Autodesk Fusion 360 part; units mm, degrees
(part 7 of 8)
equation "d2050 = ( ( layoutGap + keycapSize / 2 + 1 * keyPitch ) - holderStemX ) + ( 3 mm ) - 0.5 mm"
equation "d2051 = ( ( ( keyRowOne ) - holderStemY ) + 4 mm ) + faceOriginV"
equation "d2052 = ( ( ( ( layoutGap + keycapSize / 2 + 1 * keyPitch ) - holderStemX ) + ( 3 mm ) - 0.5 mm ) + ( 1 mm ) ) - ( ( ( layoutGap + keycapSize / 2 + 1 * keyPitch ) - holderStemX ) + ( 3 mm ) - 0.5 mm )"
equation "d2053 = ( ( ( ( ( keyRowOne ) - holderStemY ) + 4 mm ) + faceOriginV ) + ( holderFrameY / 2 - 4 mm ) ) - ( ( ( ( keyRowOne ) - holderStemY ) + 4 mm ) + faceOriginV )"
equation "d2056 = ( ( layoutGap + keycapSize / 2 + 1 * keyPitch ) - holderStemX ) - holderFrameX / 2 - 0.1 mm"
equation "d2057 = ( ( ( keyRowOne ) - holderStemY ) - 5.1 mm ) + faceOriginV"
equation "d2058 = ( ( ( ( layoutGap + keycapSize / 2 + 1 * keyPitch ) - holderStemX ) - holderFrameX / 2 - 0.1 mm ) + ( holderFrameX / 2 - holderWidth / 2 + 0.1 mm ) ) - ( ( ( layoutGap + keycapSize / 2 + 1 * keyPitch ) - holderStemX ) - holderFrameX / 2 - 0.1 mm )"
equation "d2059 = ( ( ( ( ( keyRowOne ) - holderStemY ) - 5.1 mm ) + faceOriginV ) + ( 7.8 mm ) ) - ( ( ( ( keyRowOne ) - holderStemY ) - 5.1 mm ) + faceOriginV )"
equation "d2060 = -( holderHeight + holderHookThickness - 1.2 mm + 0.2 mm )"
equation "d2062 = ( ( layoutGap + keycapSize / 2 + 1 * keyPitch ) - holderStemX ) + holderWidth / 2"
equation "d2063 = ( ( ( keyRowOne ) - holderStemY ) - 5.1 mm ) + faceOriginV"
equation "d2064 = ( ( ( ( layoutGap + keycapSize / 2 + 1 * keyPitch ) - holderStemX ) + holderWidth / 2 ) + ( holderFrameX / 2 - holderWidth / 2 + 0.1 mm ) ) - ( ( ( layoutGap + keycapSize / 2 + 1 * keyPitch ) - holderStemX ) + holderWidth / 2 )"
equation "d2065 = ( ( ( ( ( keyRowOne ) - holderStemY ) - 5.1 mm ) + faceOriginV ) + ( 7.8 mm ) ) - ( ( ( ( keyRowOne ) - holderStemY ) - 5.1 mm ) + faceOriginV )"
equation "d2066 = -( holderHeight + holderHookThickness - 1.2 mm + 0.2 mm )"
equation "d2068 = ( ( layoutGap + keycapSize / 2 + 1 * keyPitch ) - holderStemX ) + ( -2.5 mm ) - 1.2 mm"
equation "d2069 = ( ( ( ( keyRowOne ) - holderStemY ) - 1.2 mm ) * cos(caseTilt) + ( holderBottomDepth + holderLidGap ) * sin(caseTilt) ) - 2.5 mm"
equation "d2070 = ( ( ( ( layoutGap + keycapSize / 2 + 1 * keyPitch ) - holderStemX ) + ( -2.5 mm ) - 1.2 mm ) + ( 2.4 mm ) ) - ( ( ( layoutGap + keycapSize / 2 + 1 * keyPitch ) - holderStemX ) + ( -2.5 mm ) - 1.2 mm )"
equation "d2071 = ( ( ( ( ( ( keyRowOne ) - holderStemY ) - 1.2 mm ) * cos(caseTilt) + ( holderBottomDepth + holderLidGap ) * sin(caseTilt) ) - 2.5 mm ) + ( 5 mm ) ) - ( ( ( ( ( keyRowOne ) - holderStemY ) - 1.2 mm ) * cos(caseTilt) + ( holderBottomDepth + holderLidGap ) * sin(caseTilt) ) - 2.5 mm )"
equation "d2072 = ( frontHeight + ( ( ( keyRowOne ) - holderStemY ) - 1.2 mm ) * sin(caseTilt) - ( holderBottomDepth + holderLidGap ) * cos(caseTilt) ) - bottomThickness - 2 mm"
equation "d2074 = ( ( layoutGap + keycapSize / 2 + 1 * keyPitch ) - holderStemX ) + ( -2.5 mm ) - 0.5 mm"
equation "d2075 = ( ( ( ( keyRowOne ) - holderStemY ) - 1.2 mm ) * cos(caseTilt) + ( holderBottomDepth + holderLidGap ) * sin(caseTilt) ) - 1.5 mm"
equation "d2076 = ( ( ( ( layoutGap + keycapSize / 2 + 1 * keyPitch ) - holderStemX ) + ( -2.5 mm ) - 0.5 mm ) + ( 1 mm ) ) - ( ( ( layoutGap + keycapSize / 2 + 1 * keyPitch ) - holderStemX ) + ( -2.5 mm ) - 0.5 mm )"
equation "d2077 = ( ( ( ( ( ( keyRowOne ) - holderStemY ) - 1.2 mm ) * cos(caseTilt) + ( holderBottomDepth + holderLidGap ) * sin(caseTilt) ) - 1.5 mm ) + ( 3 mm ) ) - ( ( ( ( ( keyRowOne ) - holderStemY ) - 1.2 mm ) * cos(caseTilt) + ( holderBottomDepth + holderLidGap ) * sin(caseTilt) ) - 1.5 mm )"
equation "d2078 = ( frontHeight + ( ( ( keyRowOne ) - holderStemY ) - 1.2 mm ) * sin(caseTilt) - ( holderBottomDepth + holderLidGap ) * cos(caseTilt) ) - bottomThickness + 0.5 mm"
equation "d2080 = ( ( ( layoutGap + keycapSize / 2 + 1 * keyPitch ) - holderStemX ) + ( -2.5 mm ) - 0.5 mm ) - 0.1 mm"
equation "d2081 = ( ( ( ( keyRowOne ) - holderStemY ) - 1.2 mm ) - 2 mm ) + faceOriginV"
equation "d2082 = ( ( ( ( ( layoutGap + keycapSize / 2 + 1 * keyPitch ) - holderStemX ) + ( -2.5 mm ) - 0.5 mm ) - 0.1 mm ) + ( 1.2 mm ) ) - ( ( ( ( layoutGap + keycapSize / 2 + 1 * keyPitch ) - holderStemX ) + ( -2.5 mm ) - 0.5 mm ) - 0.1 mm )"
equation "d2083 = ( ( ( ( ( ( keyRowOne ) - holderStemY ) - 1.2 mm ) - 2 mm ) + faceOriginV ) + ( 4 mm ) ) - ( ( ( ( ( keyRowOne ) - holderStemY ) - 1.2 mm ) - 2 mm ) + faceOriginV )"
equation "d2084 = rearHeight"
equation "d2086 = ( ( layoutGap + keycapSize / 2 + 1 * keyPitch ) - holderStemX ) + ( 2.5 mm ) - 1.2 mm"
equation "d2087 = ( ( ( ( keyRowOne ) - holderStemY ) - 1.2 mm ) * cos(caseTilt) + ( holderBottomDepth + holderLidGap ) * sin(caseTilt) ) - 2.5 mm"
equation "d2088 = ( ( ( ( layoutGap + keycapSize / 2 + 1 * keyPitch ) - holderStemX ) + ( 2.5 mm ) - 1.2 mm ) + ( 2.4 mm ) ) - ( ( ( layoutGap + keycapSize / 2 + 1 * keyPitch ) - holderStemX ) + ( 2.5 mm ) - 1.2 mm )"
equation "d2089 = ( ( ( ( ( ( keyRowOne ) - holderStemY ) - 1.2 mm ) * cos(caseTilt) + ( holderBottomDepth + holderLidGap ) * sin(caseTilt) ) - 2.5 mm ) + ( 5 mm ) ) - ( ( ( ( ( keyRowOne ) - holderStemY ) - 1.2 mm ) * cos(caseTilt) + ( holderBottomDepth + holderLidGap ) * sin(caseTilt) ) - 2.5 mm )"
equation "d2090 = ( frontHeight + ( ( ( keyRowOne ) - holderStemY ) - 1.2 mm ) * sin(caseTilt) - ( holderBottomDepth + holderLidGap ) * cos(caseTilt) ) - bottomThickness - 2 mm"
equation "d2092 = ( ( layoutGap + keycapSize / 2 + 1 * keyPitch ) - holderStemX ) + ( 2.5 mm ) - 0.5 mm"
equation "d2093 = ( ( ( ( keyRowOne ) - holderStemY ) - 1.2 mm ) * cos(caseTilt) + ( holderBottomDepth + holderLidGap ) * sin(caseTilt) ) - 1.5 mm"
equation "d2094 = ( ( ( ( layoutGap + keycapSize / 2 + 1 * keyPitch ) - holderStemX ) + ( 2.5 mm ) - 0.5 mm ) + ( 1 mm ) ) - ( ( ( layoutGap + keycapSize / 2 + 1 * keyPitch ) - holderStemX ) + ( 2.5 mm ) - 0.5 mm )"
equation "d2095 = ( ( ( ( ( ( keyRowOne ) - holderStemY ) - 1.2 mm ) * cos(caseTilt) + ( holderBottomDepth + holderLidGap ) * sin(caseTilt) ) - 1.5 mm ) + ( 3 mm ) ) - ( ( ( ( ( keyRowOne ) - holderStemY ) - 1.2 mm ) * cos(caseTilt) + ( holderBottomDepth + holderLidGap ) * sin(caseTilt) ) - 1.5 mm )"
equation "d2096 = ( frontHeight + ( ( ( keyRowOne ) - holderStemY ) - 1.2 mm ) * sin(caseTilt) - ( holderBottomDepth + holderLidGap ) * cos(caseTilt) ) - bottomThickness + 0.5 mm"
equation "d2098 = ( ( ( layoutGap + keycapSize / 2 + 1 * keyPitch ) - holderStemX ) + ( 2.5 mm ) - 0.5 mm ) - 0.1 mm"
equation "d2099 = ( ( ( ( keyRowOne ) - holderStemY ) - 1.2 mm ) - 2 mm ) + faceOriginV"
equation "d2100 = ( ( ( ( ( layoutGap + keycapSize / 2 + 1 * keyPitch ) - holderStemX ) + ( 2.5 mm ) - 0.5 mm ) - 0.1 mm ) + ( 1.2 mm ) ) - ( ( ( ( layoutGap + keycapSize / 2 + 1 * keyPitch ) - holderStemX ) + ( 2.5 mm ) - 0.5 mm ) - 0.1 mm )"
equation "d2101 = ( ( ( ( ( ( keyRowOne ) - holderStemY ) - 1.2 mm ) - 2 mm ) + faceOriginV ) + ( 4 mm ) ) - ( ( ( ( ( keyRowOne ) - holderStemY ) - 1.2 mm ) - 2 mm ) + faceOriginV )"
equation "d2102 = rearHeight"
equation "d2104 = ( layoutGap + keycapSize / 2 + 2 * keyPitch ) - holderFrameX / 2"
equation "d2105 = ( ( keyRowOne ) - holderFrameY / 2 ) + faceOriginV"
equation "d2106 = ( ( ( layoutGap + keycapSize / 2 + 2 * keyPitch ) - holderFrameX / 2 ) + ( holderFrameX ) ) - ( ( layoutGap + keycapSize / 2 + 2 * keyPitch ) - holderFrameX / 2 )"
equation "d2107 = ( ( ( ( keyRowOne ) - holderFrameY / 2 ) + faceOriginV ) + ( holderFrameY ) ) - ( ( ( keyRowOne ) - holderFrameY / 2 ) + faceOriginV )"
equation "d2108 = -( holderBottomDepth + holderHookThickness - shellWall - carrierClearance - carrierThickness )"
equation "d2110 = ( layoutGap + keycapSize / 2 + 2 * keyPitch ) - holderSwitchVoid / 2"
equation "d2111 = ( ( keyRowOne ) - holderSwitchVoid / 2 ) + faceOriginV"
equation "d2112 = ( ( ( layoutGap + keycapSize / 2 + 2 * keyPitch ) - holderSwitchVoid / 2 ) + ( holderSwitchVoid ) ) - ( ( layoutGap + keycapSize / 2 + 2 * keyPitch ) - holderSwitchVoid / 2 )"
equation "d2113 = ( ( ( ( keyRowOne ) - holderSwitchVoid / 2 ) + faceOriginV ) + ( holderSwitchVoid ) ) - ( ( ( keyRowOne ) - holderSwitchVoid / 2 ) + faceOriginV )"
equation "d2114 = -( holderTopDepth - shellWall - carrierClearance - carrierThickness )"
equation "d2116 = ( ( layoutGap + keycapSize / 2 + 2 * keyPitch ) - holderStemX ) - holderWidth / 2 - holderFit"
equation "d2117 = ( ( ( keyRowOne ) - holderStemY ) - holderLength / 2 - holderFit ) + faceOriginV"
equation "d2118 = ( ( ( ( layoutGap + keycapSize / 2 + 2 * keyPitch ) - holderStemX ) - holderWidth / 2 - holderFit ) + ( holderWidth + 2 * holderFit ) ) - ( ( ( layoutGap + keycapSize / 2 + 2 * keyPitch ) - holderStemX ) - holderWidth / 2 - holderFit )"
equation "d2119 = ( ( ( ( ( keyRowOne ) - holderStemY ) - holderLength / 2 - holderFit ) + faceOriginV ) + ( holderLength + 2 * holderFit ) ) - ( ( ( ( keyRowOne ) - holderStemY ) - holderLength / 2 - holderFit ) + faceOriginV )"
equation "d2120 = -( holderHeight + holderHookThickness + 0.2 mm )"
equation "d2122 = ( ( layoutGap + keycapSize / 2 + 2 * keyPitch ) - holderStemX ) - holderFrameX / 2 - 0.1 mm"
equation "d2123 = ( ( ( ( keyRowOne ) - holderStemY ) + holderSpringY ) - holderSpringWidth / 2 - 0.6 mm ) + faceOriginV"
equation "d2124 = ( ( ( ( layoutGap + keycapSize / 2 + 2 * keyPitch ) - holderStemX ) - holderFrameX / 2 - 0.1 mm ) + ( holderFrameX / 2 - holderWidth / 2 - holderFit + 0.1 mm ) ) - ( ( ( layoutGap + keycapSize / 2 + 2 * keyPitch ) - holderStemX ) - holderFrameX / 2 - 0.1 mm )"
equation "d2125 = ( ( ( ( ( ( keyRowOne ) - holderStemY ) + holderSpringY ) - holderSpringWidth / 2 - 0.6 mm ) + faceOriginV ) + ( 0.6 mm ) ) - ( ( ( ( ( keyRowOne ) - holderStemY ) + holderSpringY ) - holderSpringWidth / 2 - 0.6 mm ) + faceOriginV )"
equation "d2126 = -( holderBottomDepth + holderHookThickness - shellWall - carrierClearance - carrierThickness - 1 mm + 0.2 mm )"
equation "d2128 = ( ( layoutGap + keycapSize / 2 + 2 * keyPitch ) - holderStemX ) - holderFrameX / 2 - 0.1 mm"
equation "d2129 = ( ( ( ( keyRowOne ) - holderStemY ) + holderSpringY ) + holderSpringWidth / 2 ) + faceOriginV"
equation "d2130 = ( ( ( ( layoutGap + keycapSize / 2 + 2 * keyPitch ) - holderStemX ) - holderFrameX / 2 - 0.1 mm ) + ( holderFrameX / 2 - holderWidth / 2 - holderFit + 0.1 mm ) ) - ( ( ( layoutGap + keycapSize / 2 + 2 * keyPitch ) - holderStemX ) - holderFrameX / 2 - 0.1 mm )"
equation "d2131 = ( ( ( ( ( ( keyRowOne ) - holderStemY ) + holderSpringY ) + holderSpringWidth / 2 ) + faceOriginV ) + ( 0.6 mm ) ) - ( ( ( ( ( keyRowOne ) - holderStemY ) + holderSpringY ) + holderSpringWidth / 2 ) + faceOriginV )"
equation "d2132 = -( holderBottomDepth + holderHookThickness - shellWall - carrierClearance - carrierThickness - 1 mm + 0.2 mm )"
equation "d2134 = ( ( layoutGap + keycapSize / 2 + 2 * keyPitch ) - holderStemX ) - holderFrameX / 2 + 0.8 mm"
equation "d2135 = ( ( ( ( keyRowOne ) - holderStemY ) + holderSpringY ) - holderSpringWidth / 2 ) + faceOriginV"
equation "d2136 = ( ( ( ( layoutGap + keycapSize / 2 + 2 * keyPitch ) - holderStemX ) - holderFrameX / 2 + 0.8 mm ) + ( holderFrameX / 2 - 0.8 mm - holderWidth / 2 - holderFit ) ) - ( ( ( layoutGap + keycapSize / 2 + 2 * keyPitch ) - holderStemX ) - holderFrameX / 2 + 0.8 mm )"
equation "d2137 = ( ( ( ( ( ( keyRowOne ) - holderStemY ) + holderSpringY ) - holderSpringWidth / 2 ) + faceOriginV ) + ( holderSpringWidth ) ) - ( ( ( ( ( keyRowOne ) - holderStemY ) + holderSpringY ) - holderSpringWidth / 2 ) + faceOriginV )"
equation "d2138 = -( holderHeight + holderHookThickness + 0.2 mm )"
equation "d2140 = ( ( layoutGap + keycapSize / 2 + 2 * keyPitch ) - holderStemX ) - holderFrameX / 2"
equation "d2141 = ( ( ( ( keyRowOne ) - holderStemY ) + holderSpringY ) - holderSpringWidth / 2 ) + faceOriginV"
equation "d2142 = ( ( ( ( layoutGap + keycapSize / 2 + 2 * keyPitch ) - holderStemX ) - holderFrameX / 2 ) + ( holderFrameX / 2 - holderWidth / 2 + holderHookOverlap ) ) - ( ( ( layoutGap + keycapSize / 2 + 2 * keyPitch ) - holderStemX ) - holderFrameX / 2 )"
equation "d2143 = ( ( ( ( ( ( keyRowOne ) - holderStemY ) + holderSpringY ) - holderSpringWidth / 2 ) + faceOriginV ) + ( holderSpringWidth ) ) - ( ( ( ( ( keyRowOne ) - holderStemY ) + holderSpringY ) - holderSpringWidth / 2 ) + faceOriginV )"
equation "d2144 = -( holderHookThickness )"
equation "d2147 = ( ( layoutGap + keycapSize / 2 + 2 * keyPitch ) - holderStemX ) + holderWidth / 2 + holderFit"
equation "d2148 = ( ( ( ( keyRowOne ) - holderStemY ) + holderSpringY ) - holderSpringWidth / 2 - 0.6 mm ) + faceOriginV"
equation "d2149 = ( ( ( ( layoutGap + keycapSize / 2 + 2 * keyPitch ) - holderStemX ) + holderWidth / 2 + holderFit ) + ( holderFrameX / 2 - holderWidth / 2 - holderFit + 0.1 mm ) ) - ( ( ( layoutGap + keycapSize / 2 + 2 * keyPitch ) - holderStemX ) + holderWidth / 2 + holderFit )"
equation "d2150 = ( ( ( ( ( ( keyRowOne ) - holderStemY ) + holderSpringY ) - holderSpringWidth / 2 - 0.6 mm ) + faceOriginV ) + ( 0.6 mm ) ) - ( ( ( ( ( keyRowOne ) - holderStemY ) + holderSpringY ) - holderSpringWidth / 2 - 0.6 mm ) + faceOriginV )"
equation "d2151 = -( holderBottomDepth + holderHookThickness - shellWall - carrierClearance - carrierThickness - 1 mm + 0.2 mm )"
equation "d2153 = ( ( layoutGap + keycapSize / 2 + 2 * keyPitch ) - holderStemX ) + holderWidth / 2 + holderFit"
equation "d2154 = ( ( ( ( keyRowOne ) - holderStemY ) + holderSpringY ) + holderSpringWidth / 2 ) + faceOriginV"
equation "d2155 = ( ( ( ( layoutGap + keycapSize / 2 + 2 * keyPitch ) - holderStemX ) + holderWidth / 2 + holderFit ) + ( holderFrameX / 2 - holderWidth / 2 - holderFit + 0.1 mm ) ) - ( ( ( layoutGap + keycapSize / 2 + 2 * keyPitch ) - holderStemX ) + holderWidth / 2 + holderFit )"
equation "d2156 = ( ( ( ( ( ( keyRowOne ) - holderStemY ) + holderSpringY ) + holderSpringWidth / 2 ) + faceOriginV ) + ( 0.6 mm ) ) - ( ( ( ( ( keyRowOne ) - holderStemY ) + holderSpringY ) + holderSpringWidth / 2 ) + faceOriginV )"
equation "d2157 = -( holderBottomDepth + holderHookThickness - shellWall - carrierClearance - carrierThickness - 1 mm + 0.2 mm )"
equation "d2159 = ( ( layoutGap + keycapSize / 2 + 2 * keyPitch ) - holderStemX ) + holderWidth / 2 + holderFit"
equation "d2160 = ( ( ( ( keyRowOne ) - holderStemY ) + holderSpringY ) - holderSpringWidth / 2 ) + faceOriginV"
equation "d2161 = ( ( ( ( layoutGap + keycapSize / 2 + 2 * keyPitch ) - holderStemX ) + holderWidth / 2 + holderFit ) + ( holderFrameX / 2 - 0.8 mm - holderWidth / 2 - holderFit ) ) - ( ( ( layoutGap + keycapSize / 2 + 2 * keyPitch ) - holderStemX ) + holderWidth / 2 + holderFit )"
equation "d2162 = ( ( ( ( ( ( keyRowOne ) - holderStemY ) + holderSpringY ) - holderSpringWidth / 2 ) + faceOriginV ) + ( holderSpringWidth ) ) - ( ( ( ( ( keyRowOne ) - holderStemY ) + holderSpringY ) - holderSpringWidth / 2 ) + faceOriginV )"
equation "d2163 = -( holderHeight + holderHookThickness + 0.2 mm )"
equation "d2165 = ( ( layoutGap + keycapSize / 2 + 2 * keyPitch ) - holderStemX ) + holderWidth / 2 - holderHookOverlap"
equation "d2166 = ( ( ( ( keyRowOne ) - holderStemY ) + holderSpringY ) - holderSpringWidth / 2 ) + faceOriginV"
equation "d2167 = ( ( ( ( layoutGap + keycapSize / 2 + 2 * keyPitch ) - holderStemX ) + holderWidth / 2 - holderHookOverlap ) + ( holderFrameX / 2 - holderWidth / 2 + holderHookOverlap ) ) - ( ( ( layoutGap + keycapSize / 2 + 2 * keyPitch ) - holderStemX ) + holderWidth / 2 - holderHookOverlap )"
equation "d2168 = ( ( ( ( ( ( keyRowOne ) - holderStemY ) + holderSpringY ) - holderSpringWidth / 2 ) + faceOriginV ) + ( holderSpringWidth ) ) - ( ( ( ( ( keyRowOne ) - holderStemY ) + holderSpringY ) - holderSpringWidth / 2 ) + faceOriginV )"
equation "d2169 = -( holderHookThickness )"
equation "d2172 = ( ( layoutGap + keycapSize / 2 + 2 * keyPitch ) - holderStemX ) + ( -3 mm ) - 0.5 mm"
equation "d2173 = ( ( ( keyRowOne ) - holderStemY ) + 4 mm ) + faceOriginV"
equation "d2174 = ( ( ( ( layoutGap + keycapSize / 2 + 2 * keyPitch ) - holderStemX ) + ( -3 mm ) - 0.5 mm ) + ( 1 mm ) ) - ( ( ( layoutGap + keycapSize / 2 + 2 * keyPitch ) - holderStemX ) + ( -3 mm ) - 0.5 mm )"
equation "d2175 = ( ( ( ( ( keyRowOne ) - holderStemY ) + 4 mm ) + faceOriginV ) + ( holderFrameY / 2 - 4 mm ) ) - ( ( ( ( keyRowOne ) - holderStemY ) + 4 mm ) + faceOriginV )"
equation "d2178 = ( ( layoutGap + keycapSize / 2 + 2 * keyPitch ) - holderStemX ) + ( 3 mm ) - 0.5 mm"
equation "d2179 = ( ( ( keyRowOne ) - holderStemY ) + 4 mm ) + faceOriginV"
equation "d2180 = ( ( ( ( layoutGap + keycapSize / 2 + 2 * keyPitch ) - holderStemX ) + ( 3 mm ) - 0.5 mm ) + ( 1 mm ) ) - ( ( ( layoutGap + keycapSize / 2 + 2 * keyPitch ) - holderStemX ) + ( 3 mm ) - 0.5 mm )"
equation "d2181 = ( ( ( ( ( keyRowOne ) - holderStemY ) + 4 mm ) + faceOriginV ) + ( holderFrameY / 2 - 4 mm ) ) - ( ( ( ( keyRowOne ) - holderStemY ) + 4 mm ) + faceOriginV )"
equation "d2184 = ( ( layoutGap + keycapSize / 2 + 2 * keyPitch ) - holderStemX ) - holderFrameX / 2 - 0.1 mm"
equation "d2185 = ( ( ( keyRowOne ) - holderStemY ) - 5.1 mm ) + faceOriginV"
equation "d2186 = ( ( ( ( layoutGap + keycapSize / 2 + 2 * keyPitch ) - holderStemX ) - holderFrameX / 2 - 0.1 mm ) + ( holderFrameX / 2 - holderWidth / 2 + 0.1 mm ) ) - ( ( ( layoutGap + keycapSize / 2 + 2 * keyPitch ) - holderStemX ) - holderFrameX / 2 - 0.1 mm )"
equation "d2187 = ( ( ( ( ( keyRowOne ) - holderStemY ) - 5.1 mm ) + faceOriginV ) + ( 7.8 mm ) ) - ( ( ( ( keyRowOne ) - holderStemY ) - 5.1 mm ) + faceOriginV )"
equation "d2188 = -( holderHeight + holderHookThickness - 1.2 mm + 0.2 mm )"
equation "d2190 = ( ( layoutGap + keycapSize / 2 + 2 * keyPitch ) - holderStemX ) + holderWidth / 2"
equation "d2191 = ( ( ( keyRowOne ) - holderStemY ) - 5.1 mm ) + faceOriginV"
equation "d2192 = ( ( ( ( layoutGap + keycapSize / 2 + 2 * keyPitch ) - holderStemX ) + holderWidth / 2 ) + ( holderFrameX / 2 - holderWidth / 2 + 0.1 mm ) ) - ( ( ( layoutGap + keycapSize / 2 + 2 * keyPitch ) - holderStemX ) + holderWidth / 2 )"
equation "d2193 = ( ( ( ( ( keyRowOne ) - holderStemY ) - 5.1 mm ) + faceOriginV ) + ( 7.8 mm ) ) - ( ( ( ( keyRowOne ) - holderStemY ) - 5.1 mm ) + faceOriginV )"
equation "d2194 = -( holderHeight + holderHookThickness - 1.2 mm + 0.2 mm )"
equation "d2196 = ( ( layoutGap + keycapSize / 2 + 2 * keyPitch ) - holderStemX ) + ( -2.5 mm ) - 1.2 mm"
equation "d2197 = ( ( ( ( keyRowOne ) - holderStemY ) - 1.2 mm ) * cos(caseTilt) + ( holderBottomDepth + holderLidGap ) * sin(caseTilt) ) - 2.5 mm"
equation "d2198 = ( ( ( ( layoutGap + keycapSize / 2 + 2 * keyPitch ) - holderStemX ) + ( -2.5 mm ) - 1.2 mm ) + ( 2.4 mm ) ) - ( ( ( layoutGap + keycapSize / 2 + 2 * keyPitch ) - holderStemX ) + ( -2.5 mm ) - 1.2 mm )"
equation "d2199 = ( ( ( ( ( ( keyRowOne ) - holderStemY ) - 1.2 mm ) * cos(caseTilt) + ( holderBottomDepth + holderLidGap ) * sin(caseTilt) ) - 2.5 mm ) + ( 5 mm ) ) - ( ( ( ( ( keyRowOne ) - holderStemY ) - 1.2 mm ) * cos(caseTilt) + ( holderBottomDepth + holderLidGap ) * sin(caseTilt) ) - 2.5 mm )"
equation "d2200 = ( frontHeight + ( ( ( keyRowOne ) - holderStemY ) - 1.2 mm ) * sin(caseTilt) - ( holderBottomDepth + holderLidGap ) * cos(caseTilt) ) - bottomThickness - 2 mm"
equation "d2202 = ( ( layoutGap + keycapSize / 2 + 2 * keyPitch ) - holderStemX ) + ( -2.5 mm ) - 0.5 mm"
equation "d2203 = ( ( ( ( keyRowOne ) - holderStemY ) - 1.2 mm ) * cos(caseTilt) + ( holderBottomDepth + holderLidGap ) * sin(caseTilt) ) - 1.5 mm"
equation "d2204 = ( ( ( ( layoutGap + keycapSize / 2 + 2 * keyPitch ) - holderStemX ) + ( -2.5 mm ) - 0.5 mm ) + ( 1 mm ) ) - ( ( ( layoutGap + keycapSize / 2 + 2 * keyPitch ) - holderStemX ) + ( -2.5 mm ) - 0.5 mm )"
equation "d2205 = ( ( ( ( ( ( keyRowOne ) - holderStemY ) - 1.2 mm ) * cos(caseTilt) + ( holderBottomDepth + holderLidGap ) * sin(caseTilt) ) - 1.5 mm ) + ( 3 mm ) ) - ( ( ( ( ( keyRowOne ) - holderStemY ) - 1.2 mm ) * cos(caseTilt) + ( holderBottomDepth + holderLidGap ) * sin(caseTilt) ) - 1.5 mm )"
equation "d2206 = ( frontHeight + ( ( ( keyRowOne ) - holderStemY ) - 1.2 mm ) * sin(caseTilt) - ( holderBottomDepth + holderLidGap ) * cos(caseTilt) ) - bottomThickness + 0.5 mm"
equation "d2208 = ( ( ( layoutGap + keycapSize / 2 + 2 * keyPitch ) - holderStemX ) + ( -2.5 mm ) - 0.5 mm ) - 0.1 mm"
equation "d2209 = ( ( ( ( keyRowOne ) - holderStemY ) - 1.2 mm ) - 2 mm ) + faceOriginV"
equation "d2210 = ( ( ( ( ( layoutGap + keycapSize / 2 + 2 * keyPitch ) - holderStemX ) + ( -2.5 mm ) - 0.5 mm ) - 0.1 mm ) + ( 1.2 mm ) ) - ( ( ( ( layoutGap + keycapSize / 2 + 2 * keyPitch ) - holderStemX ) + ( -2.5 mm ) - 0.5 mm ) - 0.1 mm )"
equation "d2211 = ( ( ( ( ( ( keyRowOne ) - holderStemY ) - 1.2 mm ) - 2 mm ) + faceOriginV ) + ( 4 mm ) ) - ( ( ( ( ( keyRowOne ) - holderStemY ) - 1.2 mm ) - 2 mm ) + faceOriginV )"
equation "d2212 = rearHeight"
equation "d2214 = ( ( layoutGap + keycapSize / 2 + 2 * keyPitch ) - holderStemX ) + ( 2.5 mm ) - 1.2 mm"
equation "d2215 = ( ( ( ( keyRowOne ) - holderStemY ) - 1.2 mm ) * cos(caseTilt) + ( holderBottomDepth + holderLidGap ) * sin(caseTilt) ) - 2.5 mm"
equation "d2216 = ( ( ( ( layoutGap + keycapSize / 2 + 2 * keyPitch ) - holderStemX ) + ( 2.5 mm ) - 1.2 mm ) + ( 2.4 mm ) ) - ( ( ( layoutGap + keycapSize / 2 + 2 * keyPitch ) - holderStemX ) + ( 2.5 mm ) - 1.2 mm )"
equation "d2217 = ( ( ( ( ( ( keyRowOne ) - holderStemY ) - 1.2 mm ) * cos(caseTilt) + ( holderBottomDepth + holderLidGap ) * sin(caseTilt) ) - 2.5 mm ) + ( 5 mm ) ) - ( ( ( ( ( keyRowOne ) - holderStemY ) - 1.2 mm ) * cos(caseTilt) + ( holderBottomDepth + holderLidGap ) * sin(caseTilt) ) - 2.5 mm )"
equation "d2218 = ( frontHeight + ( ( ( keyRowOne ) - holderStemY ) - 1.2 mm ) * sin(caseTilt) - ( holderBottomDepth + holderLidGap ) * cos(caseTilt) ) - bottomThickness - 2 mm"
equation "d2220 = ( ( layoutGap + keycapSize / 2 + 2 * keyPitch ) - holderStemX ) + ( 2.5 mm ) - 0.5 mm"
equation "d2221 = ( ( ( ( keyRowOne ) - holderStemY ) - 1.2 mm ) * cos(caseTilt) + ( holderBottomDepth + holderLidGap ) * sin(caseTilt) ) - 1.5 mm"
equation "d2222 = ( ( ( ( layoutGap + keycapSize / 2 + 2 * keyPitch ) - holderStemX ) + ( 2.5 mm ) - 0.5 mm ) + ( 1 mm ) ) - ( ( ( layoutGap + keycapSize / 2 + 2 * keyPitch ) - holderStemX ) + ( 2.5 mm ) - 0.5 mm )"
equation "d2223 = ( ( ( ( ( ( keyRowOne ) - holderStemY ) - 1.2 mm ) * cos(caseTilt) + ( holderBottomDepth + holderLidGap ) * sin(caseTilt) ) - 1.5 mm ) + ( 3 mm ) ) - ( ( ( ( ( keyRowOne ) - holderStemY ) - 1.2 mm ) * cos(caseTilt) + ( holderBottomDepth + holderLidGap ) * sin(caseTilt) ) - 1.5 mm )"
equation "d2224 = ( frontHeight + ( ( ( keyRowOne ) - holderStemY ) - 1.2 mm ) * sin(caseTilt) - ( holderBottomDepth + holderLidGap ) * cos(caseTilt) ) - bottomThickness + 0.5 mm"
equation "d2226 = ( ( ( layoutGap + keycapSize / 2 + 2 * keyPitch ) - holderStemX ) + ( 2.5 mm ) - 0.5 mm ) - 0.1 mm"
equation "d2227 = ( ( ( ( keyRowOne ) - holderStemY ) - 1.2 mm ) - 2 mm ) + faceOriginV"
equation "d2228 = ( ( ( ( ( layoutGap + keycapSize / 2 + 2 * keyPitch ) - holderStemX ) + ( 2.5 mm ) - 0.5 mm ) - 0.1 mm ) + ( 1.2 mm ) ) - ( ( ( ( layoutGap + keycapSize / 2 + 2 * keyPitch ) - holderStemX ) + ( 2.5 mm ) - 0.5 mm ) - 0.1 mm )"
equation "d2229 = ( ( ( ( ( ( keyRowOne ) - holderStemY ) - 1.2 mm ) - 2 mm ) + faceOriginV ) + ( 4 mm ) ) - ( ( ( ( ( keyRowOne ) - holderStemY ) - 1.2 mm ) - 2 mm ) + faceOriginV )"
equation "d2230 = rearHeight"
equation "d2232 = ( layoutGap + keycapSize / 2 + 0 * keyPitch ) - holderFrameX / 2"
equation "d2233 = ( ( keyRowTwo ) - holderFrameY / 2 ) + faceOriginV"
equation "d2234 = ( ( ( layoutGap + keycapSize / 2 + 0 * keyPitch ) - holderFrameX / 2 ) + ( holderFrameX ) ) - ( ( layoutGap + keycapSize / 2 + 0 * keyPitch ) - holderFrameX / 2 )"
equation "d2235 = ( ( ( ( keyRowTwo ) - holderFrameY / 2 ) + faceOriginV ) + ( holderFrameY ) ) - ( ( ( keyRowTwo ) - holderFrameY / 2 ) + faceOriginV )"
equation "d2236 = -( holderBottomDepth + holderHookThickness - shellWall - carrierClearance - carrierThickness )"
equation "d2238 = ( layoutGap + keycapSize / 2 + 0 * keyPitch ) - holderSwitchVoid / 2"
equation "d2239 = ( ( keyRowTwo ) - holderSwitchVoid / 2 ) + faceOriginV"
equation "d2240 = ( ( ( layoutGap + keycapSize / 2 + 0 * keyPitch ) - holderSwitchVoid / 2 ) + ( holderSwitchVoid ) ) - ( ( layoutGap + keycapSize / 2 + 0 * keyPitch ) - holderSwitchVoid / 2 )"
equation "d2241 = ( ( ( ( keyRowTwo ) - holderSwitchVoid / 2 ) + faceOriginV ) + ( holderSwitchVoid ) ) - ( ( ( keyRowTwo ) - holderSwitchVoid / 2 ) + faceOriginV )"
equation "d2242 = -( holderTopDepth - shellWall - carrierClearance - carrierThickness )"
equation "d2244 = ( ( layoutGap + keycapSize / 2 + 0 * keyPitch ) - holderStemX ) - holderWidth / 2 - holderFit"
equation "d2245 = ( ( ( keyRowTwo ) - holderStemY ) - holderLength / 2 - holderFit ) + faceOriginV"
equation "d2246 = ( ( ( ( layoutGap + keycapSize / 2 + 0 * keyPitch ) - holderStemX ) - holderWidth / 2 - holderFit ) + ( holderWidth + 2 * holderFit ) ) - ( ( ( layoutGap + keycapSize / 2 + 0 * keyPitch ) - holderStemX ) - holderWidth / 2 - holderFit )"
equation "d2247 = ( ( ( ( ( keyRowTwo ) - holderStemY ) - holderLength / 2 - holderFit ) + faceOriginV ) + ( holderLength + 2 * holderFit ) ) - ( ( ( ( keyRowTwo ) - holderStemY ) - holderLength / 2 - holderFit ) + faceOriginV )"
equation "d2248 = -( holderHeight + holderHookThickness + 0.2 mm )"
equation "d2250 = ( ( layoutGap + keycapSize / 2 + 0 * keyPitch ) - holderStemX ) - holderFrameX / 2 - 0.1 mm"
equation "d2251 = ( ( ( ( keyRowTwo ) - holderStemY ) + holderSpringY ) - holderSpringWidth / 2 - 0.6 mm ) + faceOriginV"
equation "d2252 = ( ( ( ( layoutGap + keycapSize / 2 + 0 * keyPitch ) - holderStemX ) - holderFrameX / 2 - 0.1 mm ) + ( holderFrameX / 2 - holderWidth / 2 - holderFit + 0.1 mm ) ) - ( ( ( layoutGap + keycapSize / 2 + 0 * keyPitch ) - holderStemX ) - holderFrameX / 2 - 0.1 mm )"
equation "d2253 = ( ( ( ( ( ( keyRowTwo ) - holderStemY ) + holderSpringY ) - holderSpringWidth / 2 - 0.6 mm ) + faceOriginV ) + ( 0.6 mm ) ) - ( ( ( ( ( keyRowTwo ) - holderStemY ) + holderSpringY ) - holderSpringWidth / 2 - 0.6 mm ) + faceOriginV )"
equation "d2254 = -( holderBottomDepth + holderHookThickness - shellWall - carrierClearance - carrierThickness - 1 mm + 0.2 mm )"
equation "d2256 = ( ( layoutGap + keycapSize / 2 + 0 * keyPitch ) - holderStemX ) - holderFrameX / 2 - 0.1 mm"
equation "d2257 = ( ( ( ( keyRowTwo ) - holderStemY ) + holderSpringY ) + holderSpringWidth / 2 ) + faceOriginV"
equation "d2258 = ( ( ( ( layoutGap + keycapSize / 2 + 0 * keyPitch ) - holderStemX ) - holderFrameX / 2 - 0.1 mm ) + ( holderFrameX / 2 - holderWidth / 2 - holderFit + 0.1 mm ) ) - ( ( ( layoutGap + keycapSize / 2 + 0 * keyPitch ) - holderStemX ) - holderFrameX / 2 - 0.1 mm )"
equation "d2259 = ( ( ( ( ( ( keyRowTwo ) - holderStemY ) + holderSpringY ) + holderSpringWidth / 2 ) + faceOriginV ) + ( 0.6 mm ) ) - ( ( ( ( ( keyRowTwo ) - holderStemY ) + holderSpringY ) + holderSpringWidth / 2 ) + faceOriginV )"
equation "d2260 = -( holderBottomDepth + holderHookThickness - shellWall - carrierClearance - carrierThickness - 1 mm + 0.2 mm )"
equation "d2262 = ( ( layoutGap + keycapSize / 2 + 0 * keyPitch ) - holderStemX ) - holderFrameX / 2 + 0.8 mm"
equation "d2263 = ( ( ( ( keyRowTwo ) - holderStemY ) + holderSpringY ) - holderSpringWidth / 2 ) + faceOriginV"
equation "d2264 = ( ( ( ( layoutGap + keycapSize / 2 + 0 * keyPitch ) - holderStemX ) - holderFrameX / 2 + 0.8 mm ) + ( holderFrameX / 2 - 0.8 mm - holderWidth / 2 - holderFit ) ) - ( ( ( layoutGap + keycapSize / 2 + 0 * keyPitch ) - holderStemX ) - holderFrameX / 2 + 0.8 mm )"
equation "d2265 = ( ( ( ( ( ( keyRowTwo ) - holderStemY ) + holderSpringY ) - holderSpringWidth / 2 ) + faceOriginV ) + ( holderSpringWidth ) ) - ( ( ( ( ( keyRowTwo ) - holderStemY ) + holderSpringY ) - holderSpringWidth / 2 ) + faceOriginV )"
equation "d2266 = -( holderHeight + holderHookThickness + 0.2 mm )"
equation "d2268 = ( ( layoutGap + keycapSize / 2 + 0 * keyPitch ) - holderStemX ) - holderFrameX / 2"
equation "d2269 = ( ( ( ( keyRowTwo ) - holderStemY ) + holderSpringY ) - holderSpringWidth / 2 ) + faceOriginV"
equation "d2270 = ( ( ( ( layoutGap + keycapSize / 2 + 0 * keyPitch ) - holderStemX ) - holderFrameX / 2 ) + ( holderFrameX / 2 - holderWidth / 2 + holderHookOverlap ) ) - ( ( ( layoutGap + keycapSize / 2 + 0 * keyPitch ) - holderStemX ) - holderFrameX / 2 )"
equation "d2271 = ( ( ( ( ( ( keyRowTwo ) - holderStemY ) + holderSpringY ) - holderSpringWidth / 2 ) + faceOriginV ) + ( holderSpringWidth ) ) - ( ( ( ( ( keyRowTwo ) - holderStemY ) + holderSpringY ) - holderSpringWidth / 2 ) + faceOriginV )"
equation "d2272 = -( holderHookThickness )"
equation "d2275 = ( ( layoutGap + keycapSize / 2 + 0 * keyPitch ) - holderStemX ) + holderWidth / 2 + holderFit"
equation "d2276 = ( ( ( ( keyRowTwo ) - holderStemY ) + holderSpringY ) - holderSpringWidth / 2 - 0.6 mm ) + faceOriginV"
equation "d2277 = ( ( ( ( layoutGap + keycapSize / 2 + 0 * keyPitch ) - holderStemX ) + holderWidth / 2 + holderFit ) + ( holderFrameX / 2 - holderWidth / 2 - holderFit + 0.1 mm ) ) - ( ( ( layoutGap + keycapSize / 2 + 0 * keyPitch ) - holderStemX ) + holderWidth / 2 + holderFit )"
equation "d2278 = ( ( ( ( ( ( keyRowTwo ) - holderStemY ) + holderSpringY ) - holderSpringWidth / 2 - 0.6 mm ) + faceOriginV ) + ( 0.6 mm ) ) - ( ( ( ( ( keyRowTwo ) - holderStemY ) + holderSpringY ) - holderSpringWidth / 2 - 0.6 mm ) + faceOriginV )"
equation "d2279 = -( holderBottomDepth + holderHookThickness - shellWall - carrierClearance - carrierThickness - 1 mm + 0.2 mm )"
equation "d2281 = ( ( layoutGap + keycapSize / 2 + 0 * keyPitch ) - holderStemX ) + holderWidth / 2 + holderFit"
equation "d2282 = ( ( ( ( keyRowTwo ) - holderStemY ) + holderSpringY ) + holderSpringWidth / 2 ) + faceOriginV"
equation "d2283 = ( ( ( ( layoutGap + keycapSize / 2 + 0 * keyPitch ) - holderStemX ) + holderWidth / 2 + holderFit ) + ( holderFrameX / 2 - holderWidth / 2 - holderFit + 0.1 mm ) ) - ( ( ( layoutGap + keycapSize / 2 + 0 * keyPitch ) - holderStemX ) + holderWidth / 2 + holderFit )"
equation "d2284 = ( ( ( ( ( ( keyRowTwo ) - holderStemY ) + holderSpringY ) + holderSpringWidth / 2 ) + faceOriginV ) + ( 0.6 mm ) ) - ( ( ( ( ( keyRowTwo ) - holderStemY ) + holderSpringY ) + holderSpringWidth / 2 ) + faceOriginV )"
equation "d2285 = -( holderBottomDepth + holderHookThickness - shellWall - carrierClearance - carrierThickness - 1 mm + 0.2 mm )"
equation "d2287 = ( ( layoutGap + keycapSize / 2 + 0 * keyPitch ) - holderStemX ) + holderWidth / 2 + holderFit"
equation "d2288 = ( ( ( ( keyRowTwo ) - holderStemY ) + holderSpringY ) - holderSpringWidth / 2 ) + faceOriginV"
equation "d2289 = ( ( ( ( layoutGap + keycapSize / 2 + 0 * keyPitch ) - holderStemX ) + holderWidth / 2 + holderFit ) + ( holderFrameX / 2 - 0.8 mm - holderWidth / 2 - holderFit ) ) - ( ( ( layoutGap + keycapSize / 2 + 0 * keyPitch ) - holderStemX ) + holderWidth / 2 + holderFit )"
equation "d2290 = ( ( ( ( ( ( keyRowTwo ) - holderStemY ) + holderSpringY ) - holderSpringWidth / 2 ) + faceOriginV ) + ( holderSpringWidth ) ) - ( ( ( ( ( keyRowTwo ) - holderStemY ) + holderSpringY ) - holderSpringWidth / 2 ) + faceOriginV )"
equation "d2291 = -( holderHeight + holderHookThickness + 0.2 mm )"
equation "d2293 = ( ( layoutGap + keycapSize / 2 + 0 * keyPitch ) - holderStemX ) + holderWidth / 2 - holderHookOverlap"
equation "d2294 = ( ( ( ( keyRowTwo ) - holderStemY ) + holderSpringY ) - holderSpringWidth / 2 ) + faceOriginV"
equation "d2295 = ( ( ( ( layoutGap + keycapSize / 2 + 0 * keyPitch ) - holderStemX ) + holderWidth / 2 - holderHookOverlap ) + ( holderFrameX / 2 - holderWidth / 2 + holderHookOverlap ) ) - ( ( ( layoutGap + keycapSize / 2 + 0 * keyPitch ) - holderStemX ) + holderWidth / 2 - holderHookOverlap )"
equation "d2296 = ( ( ( ( ( ( keyRowTwo ) - holderStemY ) + holderSpringY ) - holderSpringWidth / 2 ) + faceOriginV ) + ( holderSpringWidth ) ) - ( ( ( ( ( keyRowTwo ) - holderStemY ) + holderSpringY ) - holderSpringWidth / 2 ) + faceOriginV )"
equation "d2297 = -( holderHookThickness )"
equation "d2300 = ( ( layoutGap + keycapSize / 2 + 0 * keyPitch ) - holderStemX ) + ( -3 mm ) - 0.5 mm"
equation "d2301 = ( ( ( keyRowTwo ) - holderStemY ) + 4 mm ) + faceOriginV"
equation "d2302 = ( ( ( ( layoutGap + keycapSize / 2 + 0 * keyPitch ) - holderStemX ) + ( -3 mm ) - 0.5 mm ) + ( 1 mm ) ) - ( ( ( layoutGap + keycapSize / 2 + 0 * keyPitch ) - holderStemX ) + ( -3 mm ) - 0.5 mm )"
equation "d2303 = ( ( ( ( ( keyRowTwo ) - holderStemY ) + 4 mm ) + faceOriginV ) + ( holderFrameY / 2 - 4 mm ) ) - ( ( ( ( keyRowTwo ) - holderStemY ) + 4 mm ) + faceOriginV )"
equation "d2306 = ( ( layoutGap + keycapSize / 2 + 0 * keyPitch ) - holderStemX ) + ( 3 mm ) - 0.5 mm"
equation "d2307 = ( ( ( keyRowTwo ) - holderStemY ) + 4 mm ) + faceOriginV"
equation "d2308 = ( ( ( ( layoutGap + keycapSize / 2 + 0 * keyPitch ) - holderStemX ) + ( 3 mm ) - 0.5 mm ) + ( 1 mm ) ) - ( ( ( layoutGap + keycapSize / 2 + 0 * keyPitch ) - holderStemX ) + ( 3 mm ) - 0.5 mm )"
equation "d2309 = ( ( ( ( ( keyRowTwo ) - holderStemY ) + 4 mm ) + faceOriginV ) + ( holderFrameY / 2 - 4 mm ) ) - ( ( ( ( keyRowTwo ) - holderStemY ) + 4 mm ) + faceOriginV )"
equation "d2312 = ( ( layoutGap + keycapSize / 2 + 0 * keyPitch ) - holderStemX ) - holderFrameX / 2 - 0.1 mm"
equation "d2313 = ( ( ( keyRowTwo ) - holderStemY ) - 5.1 mm ) + faceOriginV"
equation "d2314 = ( ( ( ( layoutGap + keycapSize / 2 + 0 * keyPitch ) - holderStemX ) - holderFrameX / 2 - 0.1 mm ) + ( holderFrameX / 2 - holderWidth / 2 + 0.1 mm ) ) - ( ( ( layoutGap + keycapSize / 2 + 0 * keyPitch ) - holderStemX ) - holderFrameX / 2 - 0.1 mm )"
equation "d2315 = ( ( ( ( ( keyRowTwo ) - holderStemY ) - 5.1 mm ) + faceOriginV ) + ( 7.8 mm ) ) - ( ( ( ( keyRowTwo ) - holderStemY ) - 5.1 mm ) + faceOriginV )"
equation "d2316 = -( holderHeight + holderHookThickness - 1.2 mm + 0.2 mm )"
equation "d2318 = ( ( layoutGap + keycapSize / 2 + 0 * keyPitch ) - holderStemX ) + holderWidth / 2"
equation "d2319 = ( ( ( keyRowTwo ) - holderStemY ) - 5.1 mm ) + faceOriginV"
equation "d2320 = ( ( ( ( layoutGap + keycapSize / 2 + 0 * keyPitch ) - holderStemX ) + holderWidth / 2 ) + ( holderFrameX / 2 - holderWidth / 2 + 0.1 mm ) ) - ( ( ( layoutGap + keycapSize / 2 + 0 * keyPitch ) - holderStemX ) + holderWidth / 2 )"
equation "d2321 = ( ( ( ( ( keyRowTwo ) - holderStemY ) - 5.1 mm ) + faceOriginV ) + ( 7.8 mm ) ) - ( ( ( ( keyRowTwo ) - holderStemY ) - 5.1 mm ) + faceOriginV )"
equation "d2322 = -( holderHeight + holderHookThickness - 1.2 mm + 0.2 mm )"
equation "d2324 = ( ( layoutGap + keycapSize / 2 + 0 * keyPitch ) - holderStemX ) + ( -2.5 mm ) - 1.2 mm"
equation "d2325 = ( ( ( ( keyRowTwo ) - holderStemY ) - 1.2 mm ) * cos(caseTilt) + ( holderBottomDepth + holderLidGap ) * sin(caseTilt) ) - 2.5 mm"
equation "d2326 = ( ( ( ( layoutGap + keycapSize / 2 + 0 * keyPitch ) - holderStemX ) + ( -2.5 mm ) - 1.2 mm ) + ( 2.4 mm ) ) - ( ( ( layoutGap + keycapSize / 2 + 0 * keyPitch ) - holderStemX ) + ( -2.5 mm ) - 1.2 mm )"
equation "d2327 = ( ( ( ( ( ( keyRowTwo ) - holderStemY ) - 1.2 mm ) * cos(caseTilt) + ( holderBottomDepth + holderLidGap ) * sin(caseTilt) ) - 2.5 mm ) + ( 5 mm ) ) - ( ( ( ( ( keyRowTwo ) - holderStemY ) - 1.2 mm ) * cos(caseTilt) + ( holderBottomDepth + holderLidGap ) * sin(caseTilt) ) - 2.5 mm )"
equation "d2328 = ( frontHeight + ( ( ( keyRowTwo ) - holderStemY ) - 1.2 mm ) * sin(caseTilt) - ( holderBottomDepth + holderLidGap ) * cos(caseTilt) ) - bottomThickness - 2 mm"
equation "d2330 = ( ( layoutGap + keycapSize / 2 + 0 * keyPitch ) - holderStemX ) + ( -2.5 mm ) - 0.5 mm"
equation "d2331 = ( ( ( ( keyRowTwo ) - holderStemY ) - 1.2 mm ) * cos(caseTilt) + ( holderBottomDepth + holderLidGap ) * sin(caseTilt) ) - 1.5 mm"
equation "d2332 = ( ( ( ( layoutGap + keycapSize / 2 + 0 * keyPitch ) - holderStemX ) + ( -2.5 mm ) - 0.5 mm ) + ( 1 mm ) ) - ( ( ( layoutGap + keycapSize / 2 + 0 * keyPitch ) - holderStemX ) + ( -2.5 mm ) - 0.5 mm )"
equation "d2333 = ( ( ( ( ( ( keyRowTwo ) - holderStemY ) - 1.2 mm ) * cos(caseTilt) + ( holderBottomDepth + holderLidGap ) * sin(caseTilt) ) - 1.5 mm ) + ( 3 mm ) ) - ( ( ( ( ( keyRowTwo ) - holderStemY ) - 1.2 mm ) * cos(caseTilt) + ( holderBottomDepth + holderLidGap ) * sin(caseTilt) ) - 1.5 mm )"
equation "d2334 = ( frontHeight + ( ( ( keyRowTwo ) - holderStemY ) - 1.2 mm ) * sin(caseTilt) - ( holderBottomDepth + holderLidGap ) * cos(caseTilt) ) - bottomThickness + 0.5 mm"
equation "d2336 = ( ( ( layoutGap + keycapSize / 2 + 0 * keyPitch ) - holderStemX ) + ( -2.5 mm ) - 0.5 mm ) - 0.1 mm"
equation "d2337 = ( ( ( ( keyRowTwo ) - holderStemY ) - 1.2 mm ) - 2 mm ) + faceOriginV"
equation "d2338 = ( ( ( ( ( layoutGap + keycapSize / 2 + 0 * keyPitch ) - holderStemX ) + ( -2.5 mm ) - 0.5 mm ) - 0.1 mm ) + ( 1.2 mm ) ) - ( ( ( ( layoutGap + keycapSize / 2 + 0 * keyPitch ) - holderStemX ) + ( -2.5 mm ) - 0.5 mm ) - 0.1 mm )"
equation "d2339 = ( ( ( ( ( ( keyRowTwo ) - holderStemY ) - 1.2 mm ) - 2 mm ) + faceOriginV ) + ( 4 mm ) ) - ( ( ( ( ( keyRowTwo ) - holderStemY ) - 1.2 mm ) - 2 mm ) + faceOriginV )"
equation "d2340 = rearHeight"
equation "d2342 = ( ( layoutGap + keycapSize / 2 + 0 * keyPitch ) - holderStemX ) + ( 2.5 mm ) - 1.2 mm"
equation "d2343 = ( ( ( ( keyRowTwo ) - holderStemY ) - 1.2 mm ) * cos(caseTilt) + ( holderBottomDepth + holderLidGap ) * sin(caseTilt) ) - 2.5 mm"
equation "d2344 = ( ( ( ( layoutGap + keycapSize / 2 + 0 * keyPitch ) - holderStemX ) + ( 2.5 mm ) - 1.2 mm ) + ( 2.4 mm ) ) - ( ( ( layoutGap + keycapSize / 2 + 0 * keyPitch ) - holderStemX ) + ( 2.5 mm ) - 1.2 mm )"
equation "d2345 = ( ( ( ( ( ( keyRowTwo ) - holderStemY ) - 1.2 mm ) * cos(caseTilt) + ( holderBottomDepth + holderLidGap ) * sin(caseTilt) ) - 2.5 mm ) + ( 5 mm ) ) - ( ( ( ( ( keyRowTwo ) - holderStemY ) - 1.2 mm ) * cos(caseTilt) + ( holderBottomDepth + holderLidGap ) * sin(caseTilt) ) - 2.5 mm )"
equation "d2346 = ( frontHeight + ( ( ( keyRowTwo ) - holderStemY ) - 1.2 mm ) * sin(caseTilt) - ( holderBottomDepth + holderLidGap ) * cos(caseTilt) ) - bottomThickness - 2 mm"
equation "d2348 = ( ( layoutGap + keycapSize / 2 + 0 * keyPitch ) - holderStemX ) + ( 2.5 mm ) - 0.5 mm"
equation "d2349 = ( ( ( ( keyRowTwo ) - holderStemY ) - 1.2 mm ) * cos(caseTilt) + ( holderBottomDepth + holderLidGap ) * sin(caseTilt) ) - 1.5 mm"
equation "d2350 = ( ( ( ( layoutGap + keycapSize / 2 + 0 * keyPitch ) - holderStemX ) + ( 2.5 mm ) - 0.5 mm ) + ( 1 mm ) ) - ( ( ( layoutGap + keycapSize / 2 + 0 * keyPitch ) - holderStemX ) + ( 2.5 mm ) - 0.5 mm )"
equation "d2351 = ( ( ( ( ( ( keyRowTwo ) - holderStemY ) - 1.2 mm ) * cos(caseTilt) + ( holderBottomDepth + holderLidGap ) * sin(caseTilt) ) - 1.5 mm ) + ( 3 mm ) ) - ( ( ( ( ( keyRowTwo ) - holderStemY ) - 1.2 mm ) * cos(caseTilt) + ( holderBottomDepth + holderLidGap ) * sin(caseTilt) ) - 1.5 mm )"
equation "d2352 = ( frontHeight + ( ( ( keyRowTwo ) - holderStemY ) - 1.2 mm ) * sin(caseTilt) - ( holderBottomDepth + holderLidGap ) * cos(caseTilt) ) - bottomThickness + 0.5 mm"
equation "d2354 = ( ( ( layoutGap + keycapSize / 2 + 0 * keyPitch ) - holderStemX ) + ( 2.5 mm ) - 0.5 mm ) - 0.1 mm"
equation "d2355 = ( ( ( ( keyRowTwo ) - holderStemY ) - 1.2 mm ) - 2 mm ) + faceOriginV"
equation "d2356 = ( ( ( ( ( layoutGap + keycapSize / 2 + 0 * keyPitch ) - holderStemX ) + ( 2.5 mm ) - 0.5 mm ) - 0.1 mm ) + ( 1.2 mm ) ) - ( ( ( ( layoutGap + keycapSize / 2 + 0 * keyPitch ) - holderStemX ) + ( 2.5 mm ) - 0.5 mm ) - 0.1 mm )"
equation "d2357 = ( ( ( ( ( ( keyRowTwo ) - holderStemY ) - 1.2 mm ) - 2 mm ) + faceOriginV ) + ( 4 mm ) ) - ( ( ( ( ( keyRowTwo ) - holderStemY ) - 1.2 mm ) - 2 mm ) + faceOriginV )"
equation "d2358 = rearHeight"
equation "d2360 = ( layoutGap + keycapSize / 2 + 1 * keyPitch ) - holderFrameX / 2"
equation "d2361 = ( ( keyRowTwo ) - holderFrameY / 2 ) + faceOriginV"
equation "d2362 = ( ( ( layoutGap + keycapSize / 2 + 1 * keyPitch ) - holderFrameX / 2 ) + ( holderFrameX ) ) - ( ( layoutGap + keycapSize / 2 + 1 * keyPitch ) - holderFrameX / 2 )"
equation "d2363 = ( ( ( ( keyRowTwo ) - holderFrameY / 2 ) + faceOriginV ) + ( holderFrameY ) ) - ( ( ( keyRowTwo ) - holderFrameY / 2 ) + faceOriginV )"
equation "d2364 = -( holderBottomDepth + holderHookThickness - shellWall - carrierClearance - carrierThickness )"
equation "d2366 = ( layoutGap + keycapSize / 2 + 1 * keyPitch ) - holderSwitchVoid / 2"
equation "d2367 = ( ( keyRowTwo ) - holderSwitchVoid / 2 ) + faceOriginV"
equation "d2368 = ( ( ( layoutGap + keycapSize / 2 + 1 * keyPitch ) - holderSwitchVoid / 2 ) + ( holderSwitchVoid ) ) - ( ( layoutGap + keycapSize / 2 + 1 * keyPitch ) - holderSwitchVoid / 2 )"
equation "d2369 = ( ( ( ( keyRowTwo ) - holderSwitchVoid / 2 ) + faceOriginV ) + ( holderSwitchVoid ) ) - ( ( ( keyRowTwo ) - holderSwitchVoid / 2 ) + faceOriginV )"
equation "d2370 = -( holderTopDepth - shellWall - carrierClearance - carrierThickness )"
equation "d2372 = ( ( layoutGap + keycapSize / 2 + 1 * keyPitch ) - holderStemX ) - holderWidth / 2 - holderFit"
equation "d2373 = ( ( ( keyRowTwo ) - holderStemY ) - holderLength / 2 - holderFit ) + faceOriginV"
equation "d2374 = ( ( ( ( layoutGap + keycapSize / 2 + 1 * keyPitch ) - holderStemX ) - holderWidth / 2 - holderFit ) + ( holderWidth + 2 * holderFit ) ) - ( ( ( layoutGap + keycapSize / 2 + 1 * keyPitch ) - holderStemX ) - holderWidth / 2 - holderFit )"
equation "d2375 = ( ( ( ( ( keyRowTwo ) - holderStemY ) - holderLength / 2 - holderFit ) + faceOriginV ) + ( holderLength + 2 * holderFit ) ) - ( ( ( ( keyRowTwo ) - holderStemY ) - holderLength / 2 - holderFit ) + faceOriginV )"
equation "d2376 = -( holderHeight + holderHookThickness + 0.2 mm )"
equation "d2378 = ( ( layoutGap + keycapSize / 2 + 1 * keyPitch ) - holderStemX ) - holderFrameX / 2 - 0.1 mm"
equation "d2379 = ( ( ( ( keyRowTwo ) - holderStemY ) + holderSpringY ) - holderSpringWidth / 2 - 0.6 mm ) + faceOriginV"
equation "d2380 = ( ( ( ( layoutGap + keycapSize / 2 + 1 * keyPitch ) - holderStemX ) - holderFrameX / 2 - 0.1 mm ) + ( holderFrameX / 2 - holderWidth / 2 - holderFit + 0.1 mm ) ) - ( ( ( layoutGap + keycapSize / 2 + 1 * keyPitch ) - holderStemX ) - holderFrameX / 2 - 0.1 mm )"
equation "d2381 = ( ( ( ( ( ( keyRowTwo ) - holderStemY ) + holderSpringY ) - holderSpringWidth / 2 - 0.6 mm ) + faceOriginV ) + ( 0.6 mm ) ) - ( ( ( ( ( keyRowTwo ) - holderStemY ) + holderSpringY ) - holderSpringWidth / 2 - 0.6 mm ) + faceOriginV )"
equation "d2382 = -( holderBottomDepth + holderHookThickness - shellWall - carrierClearance - carrierThickness - 1 mm + 0.2 mm )"
equation "d2384 = ( ( layoutGap + keycapSize / 2 + 1 * keyPitch ) - holderStemX ) - holderFrameX / 2 - 0.1 mm"
equation "d2385 = ( ( ( ( keyRowTwo ) - holderStemY ) + holderSpringY ) + holderSpringWidth / 2 ) + faceOriginV"
equation "d2386 = ( ( ( ( layoutGap + keycapSize / 2 + 1 * keyPitch ) - holderStemX ) - holderFrameX / 2 - 0.1 mm ) + ( holderFrameX / 2 - holderWidth / 2 - holderFit + 0.1 mm ) ) - ( ( ( layoutGap + keycapSize / 2 + 1 * keyPitch ) - holderStemX ) - holderFrameX / 2 - 0.1 mm )"
equation "d2387 = ( ( ( ( ( ( keyRowTwo ) - holderStemY ) + holderSpringY ) + holderSpringWidth / 2 ) + faceOriginV ) + ( 0.6 mm ) ) - ( ( ( ( ( keyRowTwo ) - holderStemY ) + holderSpringY ) + holderSpringWidth / 2 ) + faceOriginV )"
equation "d2388 = -( holderBottomDepth + holderHookThickness - shellWall - carrierClearance - carrierThickness - 1 mm + 0.2 mm )"
equation "d2390 = ( ( layoutGap + keycapSize / 2 + 1 * keyPitch ) - holderStemX ) - holderFrameX / 2 + 0.8 mm"
equation "d2391 = ( ( ( ( keyRowTwo ) - holderStemY ) + holderSpringY ) - holderSpringWidth / 2 ) + faceOriginV"
equation "d2392 = ( ( ( ( layoutGap + keycapSize / 2 + 1 * keyPitch ) - holderStemX ) - holderFrameX / 2 + 0.8 mm ) + ( holderFrameX / 2 - 0.8 mm - holderWidth / 2 - holderFit ) ) - ( ( ( layoutGap + keycapSize / 2 + 1 * keyPitch ) - holderStemX ) - holderFrameX / 2 + 0.8 mm )"
equation "d2393 = ( ( ( ( ( ( keyRowTwo ) - holderStemY ) + holderSpringY ) - holderSpringWidth / 2 ) + faceOriginV ) + ( holderSpringWidth ) ) - ( ( ( ( ( keyRowTwo ) - holderStemY ) + holderSpringY ) - holderSpringWidth / 2 ) + faceOriginV )"
equation "d2394 = -( holderHeight + holderHookThickness + 0.2 mm )"
equation "d2396 = ( ( layoutGap + keycapSize / 2 + 1 * keyPitch ) - holderStemX ) - holderFrameX / 2"
equation "d2397 = ( ( ( ( keyRowTwo ) - holderStemY ) + holderSpringY ) - holderSpringWidth / 2 ) + faceOriginV"
equation "d2398 = ( ( ( ( layoutGap + keycapSize / 2 + 1 * keyPitch ) - holderStemX ) - holderFrameX / 2 ) + ( holderFrameX / 2 - holderWidth / 2 + holderHookOverlap ) ) - ( ( ( layoutGap + keycapSize / 2 + 1 * keyPitch ) - holderStemX ) - holderFrameX / 2 )"
equation "d2399 = ( ( ( ( ( ( keyRowTwo ) - holderStemY ) + holderSpringY ) - holderSpringWidth / 2 ) + faceOriginV ) + ( holderSpringWidth ) ) - ( ( ( ( ( keyRowTwo ) - holderStemY ) + holderSpringY ) - holderSpringWidth / 2 ) + faceOriginV )"
equation "d2400 = -( holderHookThickness )"
equation "d2403 = ( ( layoutGap + keycapSize / 2 + 1 * keyPitch ) - holderStemX ) + holderWidth / 2 + holderFit"
equation "d2404 = ( ( ( ( keyRowTwo ) - holderStemY ) + holderSpringY ) - holderSpringWidth / 2 - 0.6 mm ) + faceOriginV"
equation "d2405 = ( ( ( ( layoutGap + keycapSize / 2 + 1 * keyPitch ) - holderStemX ) + holderWidth / 2 + holderFit ) + ( holderFrameX / 2 - holderWidth / 2 - holderFit + 0.1 mm ) ) - ( ( ( layoutGap + keycapSize / 2 + 1 * keyPitch ) - holderStemX ) + holderWidth / 2 + holderFit )"
equation "d2406 = ( ( ( ( ( ( keyRowTwo ) - holderStemY ) + holderSpringY ) - holderSpringWidth / 2 - 0.6 mm ) + faceOriginV ) + ( 0.6 mm ) ) - ( ( ( ( ( keyRowTwo ) - holderStemY ) + holderSpringY ) - holderSpringWidth / 2 - 0.6 mm ) + faceOriginV )"
equation "d2407 = -( holderBottomDepth + holderHookThickness - shellWall - carrierClearance - carrierThickness - 1 mm + 0.2 mm )"
equation "d2409 = ( ( layoutGap + keycapSize / 2 + 1 * keyPitch ) - holderStemX ) + holderWidth / 2 + holderFit"
equation "d2410 = ( ( ( ( keyRowTwo ) - holderStemY ) + holderSpringY ) + holderSpringWidth / 2 ) + faceOriginV"
equation "d2411 = ( ( ( ( layoutGap + keycapSize / 2 + 1 * keyPitch ) - holderStemX ) + holderWidth / 2 + holderFit ) + ( holderFrameX / 2 - holderWidth / 2 - holderFit + 0.1 mm ) ) - ( ( ( layoutGap + keycapSize / 2 + 1 * keyPitch ) - holderStemX ) + holderWidth / 2 + holderFit )"
equation "d2412 = ( ( ( ( ( ( keyRowTwo ) - holderStemY ) + holderSpringY ) + holderSpringWidth / 2 ) + faceOriginV ) + ( 0.6 mm ) ) - ( ( ( ( ( keyRowTwo ) - holderStemY ) + holderSpringY ) + holderSpringWidth / 2 ) + faceOriginV )"
equation "d2413 = -( holderBottomDepth + holderHookThickness - shellWall - carrierClearance - carrierThickness - 1 mm + 0.2 mm )"
equation "d2415 = ( ( layoutGap + keycapSize / 2 + 1 * keyPitch ) - holderStemX ) + holderWidth / 2 + holderFit"
equation "d2416 = ( ( ( ( keyRowTwo ) - holderStemY ) + holderSpringY ) - holderSpringWidth / 2 ) + faceOriginV"
equation "d2417 = ( ( ( ( layoutGap + keycapSize / 2 + 1 * keyPitch ) - holderStemX ) + holderWidth / 2 + holderFit ) + ( holderFrameX / 2 - 0.8 mm - holderWidth / 2 - holderFit ) ) - ( ( ( layoutGap + keycapSize / 2 + 1 * keyPitch ) - holderStemX ) + holderWidth / 2 + holderFit )"
equation "d2418 = ( ( ( ( ( ( keyRowTwo ) - holderStemY ) + holderSpringY ) - holderSpringWidth / 2 ) + faceOriginV ) + ( holderSpringWidth ) ) - ( ( ( ( ( keyRowTwo ) - holderStemY ) + holderSpringY ) - holderSpringWidth / 2 ) + faceOriginV )"
equation "d2419 = -( holderHeight + holderHookThickness + 0.2 mm )"
equation "d2421 = ( ( layoutGap + keycapSize / 2 + 1 * keyPitch ) - holderStemX ) + holderWidth / 2 - holderHookOverlap"
equation "d2422 = ( ( ( ( keyRowTwo ) - holderStemY ) + holderSpringY ) - holderSpringWidth / 2 ) + faceOriginV"
equation "d2423 = ( ( ( ( layoutGap + keycapSize / 2 + 1 * keyPitch ) - holderStemX ) + holderWidth / 2 - holderHookOverlap ) + ( holderFrameX / 2 - holderWidth / 2 + holderHookOverlap ) ) - ( ( ( layoutGap + keycapSize / 2 + 1 * keyPitch ) - holderStemX ) + holderWidth / 2 - holderHookOverlap )"
equation "d2424 = ( ( ( ( ( ( keyRowTwo ) - holderStemY ) + holderSpringY ) - holderSpringWidth / 2 ) + faceOriginV ) + ( holderSpringWidth ) ) - ( ( ( ( ( keyRowTwo ) - holderStemY ) + holderSpringY ) - holderSpringWidth / 2 ) + faceOriginV )"
equation "d2425 = -( holderHookThickness )"
equation "d2428 = ( ( layoutGap + keycapSize / 2 + 1 * keyPitch ) - holderStemX ) + ( -3 mm ) - 0.5 mm"
equation "d2429 = ( ( ( keyRowTwo ) - holderStemY ) + 4 mm ) + faceOriginV"
equation "d2430 = ( ( ( ( layoutGap + keycapSize / 2 + 1 * keyPitch ) - holderStemX ) + ( -3 mm ) - 0.5 mm ) + ( 1 mm ) ) - ( ( ( layoutGap + keycapSize / 2 + 1 * keyPitch ) - holderStemX ) + ( -3 mm ) - 0.5 mm )"
equation "d2431 = ( ( ( ( ( keyRowTwo ) - holderStemY ) + 4 mm ) + faceOriginV ) + ( holderFrameY / 2 - 4 mm ) ) - ( ( ( ( keyRowTwo ) - holderStemY ) + 4 mm ) + faceOriginV )"
equation "d2434 = ( ( layoutGap + keycapSize / 2 + 1 * keyPitch ) - holderStemX ) + ( 3 mm ) - 0.5 mm"
equation "d2435 = ( ( ( keyRowTwo ) - holderStemY ) + 4 mm ) + faceOriginV"
equation "d2436 = ( ( ( ( layoutGap + keycapSize / 2 + 1 * keyPitch ) - holderStemX ) + ( 3 mm ) - 0.5 mm ) + ( 1 mm ) ) - ( ( ( layoutGap + keycapSize / 2 + 1 * keyPitch ) - holderStemX ) + ( 3 mm ) - 0.5 mm )"
equation "d2437 = ( ( ( ( ( keyRowTwo ) - holderStemY ) + 4 mm ) + faceOriginV ) + ( holderFrameY / 2 - 4 mm ) ) - ( ( ( ( keyRowTwo ) - holderStemY ) + 4 mm ) + faceOriginV )"
equation "d2440 = ( ( layoutGap + keycapSize / 2 + 1 * keyPitch ) - holderStemX ) - holderFrameX / 2 - 0.1 mm"